Autodesk Inventor part; units mm, degrees
(part 2 of 3)
sketch "Sketch10" plane through (0, 7, 0) normal (0, 1, 0) x (1, 0, 0)
  line L0 (202.5, 101) -> (355.1, 101) projected
  arc A0 (358.1, 98) -> (355.1, 101) centre (355.1, 98) ccw projected
  line L1 (358.1, 98) -> (358.1, 72) projected
  arc A1 (355.1, 69) -> (358.1, 72) centre (355.1, 72) ccw projected
  line L2 (355.1, 69) -> (202.5, 69) projected
  arc A2 (199.5, 72) -> (202.5, 69) centre (202.5, 72) ccw projected
  line L3 (199.5, 72) -> (199.5, 98) projected
  arc A3 (202.5, 101) -> (199.5, 98) centre (202.5, 98) ccw projected
  circle A4 centre (375.1, 69) radius 2.9 projected
  circle A5 centre (375.1, 101) radius 2.9 projected
  circle A6 centre (182.5, 69) radius 2.9 projected
  circle A7 centre (182.5, 101) radius 2.9 projected
  arc A8 (200.9, 198.5) -> (195.1, 198.5) centre (198, 198.5) ccw projected
  line L4 (200.9, 198.5) -> (200.9, 195.5) projected
  arc A9 (195.1, 195.5) -> (200.9, 195.5) centre (198, 195.5) ccw projected
  line L5 (195.1, 195.5) -> (195.1, 198.5) projected
  line L6 (357, 193.5) -> (360, 193.5) projected
  line L7 (360, 193.5) -> (360, 173.5) projected
  line L8 (360, 173.5) -> (357, 173.5) projected
  line L9 (357, 173.5) -> (357, 193.5) projected
  line L10 (357, -3.5) -> (360, -3.5) projected
  line L11 (360, -3.5) -> (360, -23.5) projected
  line L12 (360, -23.5) -> (357, -23.5) projected
  line L13 (357, -23.5) -> (357, -3.5) projected
  line L14 (163, -23.5) -> (160, -23.5) projected
  line L15 (160, -23.5) -> (160, -3.5) projected
  line L16 (160, -3.5) -> (163, -3.5) projected
  line L17 (163, -3.5) -> (163, -23.5) projected
  arc A10 (345.5, -10.6) -> (345.5, -16.4) centre (345.5, -13.5) ccw projected
  line L18 (345.5, -10.6) -> (348.5, -10.6) projected
  arc A11 (348.5, -16.4) -> (348.5, -10.6) centre (348.5, -13.5) ccw projected
  line L19 (348.5, -16.4) -> (345.5, -16.4) projected
  line L20 (348.5, 180.6) -> (345.5, 180.6) projected
  arc A12 (345.5, 186.4) -> (345.5, 180.6) centre (345.5, 183.5) ccw projected
  line L21 (345.5, 186.4) -> (348.5, 186.4) projected
  arc A13 (348.5, 180.6) -> (348.5, 186.4) centre (348.5, 183.5) ccw projected
  arc A14 (174.5, 180.6) -> (174.5, 186.4) centre (174.5, 183.5) ccw projected
  line L22 (174.5, 180.6) -> (171.5, 180.6) projected
  arc A15 (171.5, 186.4) -> (171.5, 180.6) centre (171.5, 183.5) ccw projected
  line L23 (171.5, 186.4) -> (174.5, 186.4) projected
  line L24 (332.5, 210) -> (332.5, 207) projected
  line L25 (332.5, 207) -> (187.5, 207) projected
  line L26 (187.5, 207) -> (187.5, 210) projected
  line L27 (187.5, 210) -> (332.5, 210) projected
  arc A16 (324.9, -25.5) -> (319.1, -25.5) centre (322, -25.5) ccw projected
  line L28 (324.9, -25.5) -> (324.9, -28.5) projected
  arc A17 (319.1, -28.5) -> (324.9, -28.5) centre (322, -28.5) ccw projected
  line L29 (319.1, -28.5) -> (319.1, -25.5) projected
  line L30 (200.9, -25.5) -> (200.9, -28.5) projected
  arc A18 (195.1, -28.5) -> (200.9, -28.5) centre (198, -28.5) ccw projected
  line L31 (195.1, -28.5) -> (195.1, -25.5) projected
  arc A19 (200.9, -25.5) -> (195.1, -25.5) centre (198, -25.5) ccw projected
  line L32 (174.5, -16.4) -> (171.5, -16.4) projected
  arc A20 (171.5, -10.6) -> (171.5, -16.4) centre (171.5, -13.5) ccw projected
  line L33 (171.5, -10.6) -> (174.5, -10.6) projected
  arc A21 (174.5, -16.4) -> (174.5, -10.6) centre (174.5, -13.5) ccw projected
  line L34 (187.5, -40) -> (187.5, -37) projected
  line L35 (187.5, -37) -> (332.5, -37) projected
  line L36 (332.5, -37) -> (332.5, -40) projected
  line L37 (332.5, -40) -> (187.5, -40) projected
  line L38 (324.9, 198.5) -> (324.9, 195.5) projected
  arc A22 (319.1, 195.5) -> (324.9, 195.5) centre (322, 195.5) ccw projected
  line L39 (319.1, 195.5) -> (319.1, 198.5) projected
  arc A23 (324.9, 198.5) -> (319.1, 198.5) centre (322, 198.5) ccw projected
  line L40 (160, 193.5) -> (163, 193.5) projected
  line L41 (163, 193.5) -> (163, 173.5) projected
  line L42 (163, 173.5) -> (160, 173.5) projected
  line L43 (160, 173.5) -> (160, 193.5) projected
  line L44 (147.75, -60) -> (137.75, -60) projected
  line L45 (137.75, -60) -> (137.75, -57) projected
  line L46 (137.75, -57) -> (147.75, -57) projected
  line L47 (147.75, -57) -> (147.75, -60) projected
  line L48 (137.75, 4) -> (137.75, 7) projected
  line L49 (137.75, 7) -> (147.75, 7) projected
  line L50 (147.75, 7) -> (147.75, 4) projected
  line L51 (147.75, 4) -> (137.75, 4) projected
  line L52 (155.5, 29.5) -> (155.5, 14.5) projected
  line L53 (155.5, 14.5) -> (152.5, 14.5) projected
  line L54 (152.5, 14.5) -> (152.5, 29.5) projected
  line L55 (152.5, 29.5) -> (155.5, 29.5) projected
  line L56 (126.5, 136) -> (130.5, 136) projected
  line L57 (130.5, 136) -> (130.5, 133) projected
  line L58 (130.5, 133) -> (126.5, 133) projected
  line L59 (126.5, 133) -> (126.5, 136) projected
  line L60 (144, 156) -> (149, 156) projected
  line L61 (149, 156) -> (149, 153) projected
  line L62 (149, 153) -> (144, 153) projected
  line L63 (144, 153) -> (144, 156) projected
  circle A24 centre (118.59, 31.5) radius 1.25 projected
  line L64 (134.5, 139) -> (122.5, 139) projected
  arc A25 (122.5, 147) -> (122.5, 139) centre (122.5, 143) ccw projected
  line L65 (122.5, 147) -> (134.5, 147) projected
  arc A26 (134.5, 139) -> (134.5, 147) centre (134.5, 143) ccw projected
  line L66 (100.5, 138) -> (100.5, 148) projected
  line L67 (100.5, 148) -> (103.5, 148) projected
  line L68 (103.5, 148) -> (103.5, 138) projected
  line L69 (103.5, 138) -> (100.5, 138) projected
  line L70 (137.75, 40) -> (147.75, 40) projected
  line L71 (147.75, 40) -> (147.75, 37) projected
  line L72 (147.75, 37) -> (137.75, 37) projected
  line L73 (137.75, 37) -> (137.75, 40) projected
  line L74 (155.5, -34.5) -> (155.5, -49.5) projected
  line L75 (155.5, -49.5) -> (152.5, -49.5) projected
  line L76 (152.5, -49.5) -> (152.5, -34.5) projected
  line L77 (152.5, -34.5) -> (155.5, -34.5) projected
  line L78 (113.25, -60) -> (103.25, -60) projected
  line L79 (103.25, -60) -> (103.25, -57) projected
  line L80 (103.25, -57) -> (113.25, -57) projected
  line L81 (113.25, -57) -> (113.25, -60) projected
  line L82 (113.25, 4) -> (103.25, 4) projected
  line L83 (103.25, 4) -> (103.25, 7) projected
  line L84 (103.25, 7) -> (113.25, 7) projected
  line L85 (113.25, 7) -> (113.25, 4) projected
  line L86 (95.5, 14.5) -> (95.5, 29.5) projected
  line L87 (95.5, 29.5) -> (98.5, 29.5) projected
  line L88 (98.5, 29.5) -> (98.5, 14.5) projected
  line L89 (98.5, 14.5) -> (95.5, 14.5) projected
  line L90 (108, 156) -> (113, 156) projected
  line L91 (113, 156) -> (113, 153) projected
  line L92 (113, 153) -> (108, 153) projected
  line L93 (108, 153) -> (108, 156) projected
  line L94 (156.5, 138) -> (153.5, 138) projected
  line L95 (153.5, 138) -> (153.5, 148) projected
  line L96 (153.5, 148) -> (156.5, 148) projected
  line L97 (156.5, 148) -> (156.5, 138) projected
  circle A27 centre (132.41, 31.5) radius 1.25 projected
  line L98 (149, 130) -> (144, 130) projected
  line L99 (144, 130) -> (144, 133) projected
  line L100 (144, 133) -> (149, 133) projected
  line L101 (149, 133) -> (149, 130) projected
  line L102 (113, 130) -> (108, 130) projected
  line L103 (108, 130) -> (108, 133) projected
  line L104 (108, 133) -> (113, 133) projected
  line L105 (113, 133) -> (113, 130) projected
  line L106 (103.25, 40) -> (113.25, 40) projected
  line L107 (113.25, 40) -> (113.25, 37) projected
  line L108 (113.25, 37) -> (103.25, 37) projected
  line L109 (103.25, 37) -> (103.25, 40) projected
  arc A28 (135.5, -40) -> (140.5, -35) centre (135.5, -35) ccw projected
  line L110 (135.5, -40) -> (115.5, -40) projected
  arc A29 (110.5, -35) -> (115.5, -40) centre (115.5, -35) ccw projected
  line L111 (110.5, -35) -> (110.5, -25) projected
  arc A30 (115.5, -20) -> (110.5, -25) centre (115.5, -25) ccw projected
  line L112 (115.5, -20) -> (135.5, -20) projected
  arc A31 (140.5, -25) -> (135.5, -20) centre (135.5, -25) ccw projected
  line L113 (140.5, -25) -> (140.5, -35) projected
  line L114 (95.5, -49.5) -> (95.5, -34.5) projected
  line L115 (95.5, -34.5) -> (98.5, -34.5) projected
  line L116 (98.5, -34.5) -> (98.5, -49.5) projected
  line L117 (98.5, -49.5) -> (95.5, -49.5) projected
  circle A32 centre (32.5, 114.5) radius 2.75 projected
  circle A33 centre (32.5, 55.5) radius 2.75 projected
  circle A34 centre (-112.5, 155) radius 2.75 projected
  circle A35 centre (-47.5, 15) radius 2.75 projected
  circle A36 centre (-112.5, 15) radius 2.75 projected
  circle A37 centre (-47.5, 155) radius 2.75 projected
  circle A38 centre (-177.5, 155) radius 2.75 projected
  circle A39 centre (-177.5, 15) radius 2.75 projected
  line L118 (-407.5, 305) -> (-387.5, 305) projected
  line L119 (-387.5, 305) -> (-387.5, 285) projected
  line L120 (-387.5, 285) -> (-407.5, 285) projected
  line L121 (-407.5, 285) -> (-407.5, 305) projected
  arc A40 (-419, -122.1) -> (-419, -127.9) centre (-419, -125) ccw projected
  line L122 (-419, -122.1) -> (-416, -122.1) projected
  arc A41 (-416, -127.9) -> (-416, -122.1) centre (-416, -125) ccw projected
  line L123 (-416, -127.9) -> (-419, -127.9) projected
  arc A42 (100.4, -143.5) -> (94.6, -143.5) centre (97.5, -143.5) ccw projected
  line L124 (100.4, -143.5) -> (100.4, -146.5) projected
  arc A43 (94.6, -146.5) -> (100.4, -146.5) centre (97.5, -146.5) ccw projected
  line L125 (94.6, -146.5) -> (94.6, -143.5) projected
  line L126 (107.5, -115) -> (107.5, -135) projected
  line L127 (107.5, -135) -> (87.5, -135) projected
  line L128 (87.5, -135) -> (87.5, -115) projected
  line L129 (87.5, -115) -> (107.5, -115) projected
  arc A44 (100.4, 316.5) -> (94.6, 316.5) centre (97.5, 316.5) ccw projected
  line L130 (100.4, 316.5) -> (100.4, 313.5) projected
  arc A45 (94.6, 313.5) -> (100.4, 313.5) centre (97.5, 313.5) ccw projected
  line L131 (94.6, 313.5) -> (94.6, 316.5) projected
  arc A46 (76, 297.9) -> (76, 292.1) centre (76, 295) ccw projected
  line L132 (76, 297.9) -> (79, 297.9) projected
  arc A47 (79, 292.1) -> (79, 297.9) centre (79, 295) ccw projected
  line L133 (79, 292.1) -> (76, 292.1) projected
  arc A48 (116, -122.1) -> (116, -127.9) centre (116, -125) ccw projected
  line L134 (116, -122.1) -> (119, -122.1) projected
  arc A49 (119, -127.9) -> (119, -122.1) centre (119, -125) ccw projected
  line L135 (119, -127.9) -> (116, -127.9) projected
  line L136 (-387.5, -135) -> (-407.5, -135) projected
  line L137 (-407.5, -135) -> (-407.5, -115) projected
  line L138 (-407.5, -115) -> (-387.5, -115) projected
  line L139 (-387.5, -115) -> (-387.5, -135) projected
  arc A50 (-394.6, -143.5) -> (-400.4, -143.5) centre (-397.5, -143.5) ccw projected
  line L140 (-394.6, -143.5) -> (-394.6, -146.5) projected
  arc A51 (-400.4, -146.5) -> (-394.6, -146.5) centre (-397.5, -146.5) ccw projected
  line L141 (-400.4, -146.5) -> (-400.4, -143.5) projected
  arc A52 (-379, 297.9) -> (-379, 292.1) centre (-379, 295) ccw projected
  line L142 (-379, 297.9) -> (-376, 297.9) projected
  arc A53 (-376, 292.1) -> (-376, 297.9) centre (-376, 295) ccw projected
  line L143 (-376, 292.1) -> (-379, 292.1) projected
  arc A54 (-394.6, 276.5) -> (-400.4, 276.5) centre (-397.5, 276.5) ccw projected
  line L144 (-394.6, 276.5) -> (-394.6, 273.5) projected
  arc A55 (-400.4, 273.5) -> (-394.6, 273.5) centre (-397.5, 273.5) ccw projected
  line L145 (-400.4, 273.5) -> (-400.4, 276.5) projected
  arc A56 (-394.6, -103.5) -> (-400.4, -103.5) centre (-397.5, -103.5) ccw projected
  line L146 (-394.6, -103.5) -> (-394.6, -106.5) projected
  arc A57 (-400.4, -106.5) -> (-394.6, -106.5) centre (-397.5, -106.5) ccw projected
  line L147 (-400.4, -106.5) -> (-400.4, -103.5) projected
  arc A58 (76, -122.1) -> (76, -127.9) centre (76, -125) ccw projected
  line L148 (76, -122.1) -> (79, -122.1) projected
  arc A59 (79, -127.9) -> (79, -122.1) centre (79, -125) ccw projected
  line L149 (79, -127.9) -> (76, -127.9) projected
  arc A60 (116, 297.9) -> (116, 292.1) centre (116, 295) ccw projected
  line L150 (116, 297.9) -> (119, 297.9) projected
  arc A61 (119, 292.1) -> (119, 297.9) centre (119, 295) ccw projected
  line L151 (119, 292.1) -> (116, 292.1) projected
  line L152 (107.5, 305) -> (107.5, 285) projected
  line L153 (107.5, 285) -> (87.5, 285) projected
  line L154 (87.5, 285) -> (87.5, 305) projected
  line L155 (87.5, 305) -> (107.5, 305) projected
  arc A62 (100.4, 276.5) -> (94.6, 276.5) centre (97.5, 276.5) ccw projected
  line L156 (100.4, 276.5) -> (100.4, 273.5) projected
  arc A63 (94.6, 273.5) -> (100.4, 273.5) centre (97.5, 273.5) ccw projected
  line L157 (94.6, 273.5) -> (94.6, 276.5) projected
  arc A64 (100.4, -103.5) -> (94.6, -103.5) centre (97.5, -103.5) ccw projected
  line L158 (100.4, -103.5) -> (100.4, -106.5) projected
  arc A65 (94.6, -106.5) -> (100.4, -106.5) centre (97.5, -106.5) ccw projected
  line L159 (94.6, -106.5) -> (94.6, -103.5) projected
  arc A66 (-379, -122.1) -> (-379, -127.9) centre (-379, -125) ccw projected
  line L160 (-379, -122.1) -> (-376, -122.1) projected
  arc A67 (-376, -127.9) -> (-376, -122.1) centre (-376, -125) ccw projected
  line L161 (-376, -127.9) -> (-379, -127.9) projected
  line L162 (-416, 292.1) -> (-419, 292.1) projected
  arc A68 (-419, 297.9) -> (-419, 292.1) centre (-419, 295) ccw projected
  line L163 (-419, 297.9) -> (-416, 297.9) projected
  arc A69 (-416, 292.1) -> (-416, 297.9) centre (-416, 295) ccw projected
  line L164 (-400.4, 313.5) -> (-400.4, 316.5) projected
  arc A70 (-394.6, 316.5) -> (-400.4, 316.5) centre (-397.5, 316.5) ccw projected
  line L165 (-394.6, 316.5) -> (-394.6, 313.5) projected
  arc A71 (-400.4, 313.5) -> (-394.6, 313.5) centre (-397.5, 313.5) ccw projected
  line L166 (442.5, 340) -> (-442.5, 340) projected
  line L167 (-442.5, 340) -> (-442.5, -340) projected
  line L168 (-442.5, -340) -> (442.5, -340) projected
  line L169 (442.5, -340) -> (442.5, 340) projected
  line L170 (-407.5, -135) -> (107.5, -135)
  line L171 (107.5, -135) -> (107.5, 305)
  line L172 (107.5, 305) -> (-407.5, 305)
  line L173 (-407.5, 305) -> (-407.5, -135)
  line L174 (-402.5, -175) -> (257.5, -175)
  line L175 (257.5, -175) -> (257.5, -300)
  line L176 (257.5, -300) -> (-402.5, -300)
  line L177 (-402.5, -300) -> (-402.5, -175)
  line L178 (297.5, -100) -> (397.5, -100)
  line L179 (397.5, -100) -> (397.5, -300)
  line L180 (397.5, -300) -> (297.5, -300)
  line L181 (297.5, -300) -> (297.5, -100)
  line L182 (254.5, -178) -> (-399.5, -178)
  line L183 (-399.5, -178) -> (-399.5, -297)
  line L184 (-399.5, -297) -> (254.5, -297)
  line L185 (254.5, -297) -> (254.5, -178)
  line L186 (-402.5, -237.5) -> (257.5, -237.5) construction
  line L187 (-72.5, -300) -> (-72.5, -175) construction
  line L188 (-242.5, -297) -> (97.5, -297)
  line L189 (97.5, -297) -> (97.5, -300)
  line L190 (97.5, -300) -> (-242.5, -300)
  line L191 (-242.5, -300) -> (-242.5, -297)
  line L192 (97.5, -178) -> (97.5, -175)
  line L193 (-242.5, -175) -> (-242.5, -178)
  line L194 (214.5, -288.5) -> (214.5, -285.5) construction
  line L195 (217.4, -288.5) -> (217.4, -285.5)
  line L196 (211.6, -285.5) -> (211.6, -288.5)
  arc A72 (211.6, -288.5) -> (217.4, -288.5) centre (214.5, -288.5) ccw
  arc A73 (217.4, -285.5) -> (211.6, -285.5) centre (214.5, -285.5) ccw
  line L197 (-359.5, -288.5) -> (-359.5, -285.5) construction
  line L198 (-362.4, -288.5) -> (-362.4, -285.5)
  line L199 (-356.6, -285.5) -> (-356.6, -288.5)
  arc A74 (-362.4, -288.5) -> (-356.6, -288.5) centre (-359.5, -288.5) ccw
  arc A75 (-356.6, -285.5) -> (-362.4, -285.5) centre (-359.5, -285.5) ccw
  line L200 (214.5, -186.5) -> (214.5, -189.5) construction
  line L201 (217.4, -186.5) -> (217.4, -189.5)
  line L202 (211.6, -189.5) -> (211.6, -186.5)
  arc A76 (217.4, -186.5) -> (211.6, -186.5) centre (214.5, -186.5) ccw
  arc A77 (211.6, -189.5) -> (217.4, -189.5) centre (214.5, -189.5) ccw
  line L203 (-356.6, -189.5) -> (-356.6, -186.5)
  line L204 (-359.5, -186.5) -> (-359.5, -189.5) construction
  arc A78 (-362.4, -189.5) -> (-356.6, -189.5) centre (-359.5, -189.5) ccw
  arc A79 (-356.6, -186.5) -> (-362.4, -186.5) centre (-359.5, -186.5) ccw
  line L205 (-362.4, -186.5) -> (-362.4, -189.5)
  line L206 (254.5, -187.5) -> (257.5, -187.5)
  line L207 (257.5, -187.5) -> (257.5, -287.5)
  line L208 (257.5, -287.5) -> (254.5, -287.5)
  line L209 (254.5, -287.5) -> (254.5, -187.5)
  line L210 (243, -280) -> (246, -280) construction
  line L211 (243, -282.9) -> (246, -282.9)
  line L212 (246, -277.1) -> (243, -277.1)
  arc A80 (243, -277.1) -> (243, -282.9) centre (243, -280) ccw
  arc A81 (246, -282.9) -> (246, -277.1) centre (246, -280) ccw
  line L213 (-388, -280) -> (-391, -280) construction
  line L214 (-388, -282.9) -> (-391, -282.9)
  line L215 (-391, -277.1) -> (-388, -277.1)
  arc A82 (-388, -282.9) -> (-388, -277.1) centre (-388, -280) ccw
  arc A83 (-391, -277.1) -> (-391, -282.9) centre (-391, -280) ccw
  line L216 (243, -195) -> (246, -195) construction
  line L217 (243, -192.1) -> (246, -192.1)
  line L218 (246, -197.9) -> (243, -197.9)
  arc A84 (243, -192.1) -> (243, -197.9) centre (243, -195) ccw
  arc A85 (246, -197.9) -> (246, -192.1) centre (246, -195) ccw
  line L219 (-388, -192.1) -> (-391, -192.1)
  line L220 (-388, -195) -> (-391, -195) construction
  line L221 (-391, -197.9) -> (-388, -197.9)
  arc A86 (-388, -197.9) -> (-388, -192.1) centre (-388, -195) ccw
  arc A87 (-391, -192.1) -> (-391, -197.9) centre (-391, -195) ccw
  line L222 (-399.5, -187.5) -> (-402.5, -187.5)
  line L223 (-402.5, -287.5) -> (-399.5, -287.5)
  line L224 (394.5, -297) -> (394.5, -103)
  line L225 (394.5, -103) -> (300.5, -103)
  line L226 (300.5, -103) -> (300.5, -297)
  line L227 (300.5, -297) -> (394.5, -297)
  line L228 (347.5, -100) -> (347.5, -300) construction
  line L229 (297.5, -200) -> (397.5, -200) construction
  line L230 (322.5, -100) -> (372.5, -100)
  line L231 (372.5, -100) -> (372.5, -103)
  line L232 (372.5, -103) -> (322.5, -103)
  line L233 (322.5, -103) -> (322.5, -100)
  line L234 (315.5, -111.5) -> (315.5, -114.5) construction
  line L235 (312.6, -111.5) -> (312.6, -114.5)
  line L236 (318.4, -114.5) -> (318.4, -111.5)
  arc A88 (318.4, -111.5) -> (312.6, -111.5) centre (315.5, -111.5) ccw
  arc A89 (312.6, -114.5) -> (318.4, -114.5) centre (315.5, -114.5) ccw
  line L237 (379.5, -111.5) -> (379.5, -114.5) construction
  line L238 (382.4, -111.5) -> (382.4, -114.5)
  line L239 (376.6, -114.5) -> (376.6, -111.5)
  arc A90 (382.4, -111.5) -> (376.6, -111.5) centre (379.5, -111.5) ccw
  arc A91 (376.6, -114.5) -> (382.4, -114.5) centre (379.5, -114.5) ccw
  line L240 (372.5, -300) -> (372.5, -297)
  line L241 (322.5, -297) -> (322.5, -300)
  line L242 (315.5, -288.5) -> (315.5, -285.5) construction
  line L243 (312.6, -288.5) -> (312.6, -285.5)
  line L244 (318.4, -285.5) -> (318.4, -288.5)
  arc A92 (312.6, -288.5) -> (318.4, -288.5) centre (315.5, -288.5) ccw
  arc A93 (318.4, -285.5) -> (312.6, -285.5) centre (315.5, -285.5) ccw
  arc A94 (382.4, -285.5) -> (376.6, -285.5) centre (379.5, -285.5) ccw
  line L245 (376.6, -285.5) -> (376.6, -288.5)
  line L246 (379.5, -288.5) -> (379.5, -285.5) construction
  line L247 (382.4, -288.5) -> (382.4, -285.5)
  arc A95 (376.6, -288.5) -> (382.4, -288.5) centre (379.5, -288.5) ccw
  line L248 (297.5, -150) -> (300.5, -150)
  line L249 (300.5, -150) -> (300.5, -250)
  line L250 (300.5, -250) -> (297.5, -250)
  line L251 (297.5, -250) -> (297.5, -150)
  line L252 (309, -138) -> (312, -138) construction
  line L253 (309, -140.9) -> (312, -140.9)
  line L254 (312, -135.1) -> (309, -135.1)
  arc A96 (309, -135.1) -> (309, -140.9) centre (309, -138) ccw
  arc A97 (312, -140.9) -> (312, -135.1) centre (312, -138) ccw
  line L255 (309, -262) -> (312, -262) construction
  line L256 (309, -259.1) -> (312, -259.1)
  line L257 (312, -264.9) -> (309, -264.9)
  arc A98 (309, -259.1) -> (309, -264.9) centre (309, -262) ccw
  arc A99 (312, -264.9) -> (312, -259.1) centre (312, -262) ccw
  line L258 (397.5, -150) -> (394.5, -150)
  line L259 (394.5, -250) -> (397.5, -250)
  line L260 (386, -138) -> (383, -138) construction
  line L261 (386, -140.9) -> (383, -140.9)
  line L262 (383, -135.1) -> (386, -135.1)
  arc A100 (386, -140.9) -> (386, -135.1) centre (386, -138) ccw
  arc A101 (383, -135.1) -> (383, -140.9) centre (383, -138) ccw
  line L263 (386, -259.1) -> (383, -259.1)
  arc A102 (386, -264.9) -> (386, -259.1) centre (386, -262) ccw
  line L264 (386, -262) -> (383, -262) construction
  arc A103 (383, -259.1) -> (383, -264.9) centre (383, -262) ccw
  line L265 (383, -264.9) -> (386, -264.9)
  point P0 (0, 0)
  point P1 (214.5, -287)
  point P2 (-359.5, -287)
  point P3 (214.5, -188)
  point P4 (-359.5, -188)
  point P5 (254.5, -237.5)
  point P6 (254.5, -237.5)
  point P7 (244.5, -280)
  point P8 (-389.5, -280)
  point P9 (244.5, -195)
  point P10 (-389.5, -195)
  point P11 (347.5, -103)
  point P12 (347.5, -103)
  point P13 (315.5, -113)
  point P14 (379.5, -113)
  point P15 (315.5, -287)
  point P16 (379.5, -287)
  point P17 (300.5, -200)
  point P18 (300.5, -200)
  point P19 (310.5, -138)
  point P20 (310.5, -262)
  point P21 (384.5, -138)
  point P22 (384.5, -262)
  point P23 (322.5, -103)
  point P24 (300.5, -150)
  point P25 (-402.5, -187.5)
  point P26 (-402.5, -287.5)
  point P27 (97.5, -297)
  point P28 (97.5, -178)
  point P29 (97.5, -175)
  point P30 (-242.5, -175)
  point P31 (257.5, -187.5)
  dimension "d188" = 125
  dimension "d189" = 660
  dimension "d190" = 40
  dimension "d191" = 40
  dimension "d192" = 100
  dimension "d193" = 200
  dimension "d194" = 40
  dimension "d195" = 40
  dimension "d196" = 3
  dimension "d197" = 340
  dimension "d198" = 3
  dimension "d199" = 5.8
  dimension "d200" = 8.5
  dimension "d201" = 40
  dimension "d202" = 100
  dimension "d203" = 3
  dimension "d204" = 5.8
  dimension "d205" = 8.5
  dimension "d206" = 20
  dimension "d207" = 3
  dimension "d208" = 50
  dimension "d209" = 3
  dimension "d210" = 5.8
  dimension "d211" = 8.5
  dimension "d212" = 15
  dimension "d213" = 100
  dimension "d214" = 3
  dimension "d215" = 5.8
  dimension "d216" = 8.5
  dimension "d217" = 35
  constraints: 224 end point, 100 symmetric about line, 64 point on circle, 32 centre point, 23 parallel, 19 midpoint, 16 tangent, 9 perpendicular, 8 horizontal, 8 point on line, 4 coincident, 1 vertical, 30 other
  measures "d188" distance of L176.end L174.start
  measures "d189" distance of L175.end L176.end
  measures "d190" distance between parallel lines of L167 L177
  measures "d191" distance between parallel lines of L168 L176
  measures "d192" distance of L179.end L180.end
  measures "d193" distance of L180.end L178.start
  measures "d194" distance between parallel lines of L168 L180
  measures "d195" distance between parallel lines of L175 L181
  measures "d196" distance between parallel lines of L174 L182
  measures "d197" distance between parallel lines of L191 L189
  measures "d198" distance of L194.start L194.end
  measures "d199" diameter of A73
  measures "d200" distance from line of L184 L194.start
  measures "d201" distance between parallel lines of L185 L194
  measures "d202" distance between parallel lines of L208 L206
  measures "d203" distance of L210.start L210.end
  measures "d204" diameter of A81
  measures "d205" distance from line of L209 L210.end
  measures "d206" distance between parallel lines of L176 L210
  measures "d207" distance between parallel lines of L179 L224
  measures "d208" distance of L231.end L232.end
  measures "d209" distance of L234.start L234.end
  measures "d210" diameter of A89
  measures "d211" distance from line of L225 L234.start
  measures "d212" distance between parallel lines of L226 L234
  measures "d213" distance of L248.end L249.end
  measures "d214" distance of L252.start L252.end
  measures "d215" diameter of A97
  measures "d216" distance from line of L226 L252.start
  measures "d217" distance between parallel lines of L225 L252
extrude "Extrusion6" cut sketch "Sketch10" against normal blind 10 contours L174 L192 L182 L193 | L222 L183 L223 L177 | L175 L208 L185 L206 | L191 L184 L189 L176 | L178 L231 L225 L233 | L248 L226 L250 L181 | L179 L259 L224 L258 | L241 L227 L240 L180 | A72 L196 A73 L195 | L198 A75 L199 A74 | L201 A77 L202 A76 | A78 L205 A79 L203 | A80 L212 A81 L211 | L214 A83 L215 A82 | L217 A85 L218 A84 | A86 L221 A87 L219 | A88 L236 A89 L235 | L238 A91 L239 A90 | L243 A93 L244 A92 | L247 A95 L245 A94 | A96 L254 A97 L253 | L256 A99 L257 A98 | L261 A101 L262 A100 | A102 L265 A103 L263
sketch "Sketch11" plane through (0, 7, 0) normal (0, 1, 0) x (1, 0, 0)
  line L0 (442.5, 340) -> (-442.5, 340) projected
  line L1 (-442.5, -340) -> (442.5, -340) projected
  line L2 (-442.5, 340) -> (-435.5, 340)
  line L3 (-435.5, 340) -> (-435.5, -340)
  line L4 (-435.5, -340) -> (-442.5, -340)
  line L5 (-442.5, -340) -> (-442.5, 340)
  line L6 (-442.5, 340) -> (-435.5, 340)
  line L7 (-435.5, 340) -> (-435.5, 300)
  line L8 (-435.5, 300) -> (-442.5, 300)
  line L9 (-442.5, 300) -> (-442.5, 340)
  line L10 (-442.5, 300) -> (-435.5, 300)
  line L11 (-435.5, 300) -> (-435.5, 260)
  line L12 (-435.5, 260) -> (-442.5, 260)
  line L13 (-442.5, 260) -> (-442.5, 300)
  line L14 (0, 340) -> (0, -340) construction
  line L15 (-435.5, 220) -> (-442.5, 220)
  line L16 (-435.5, 180) -> (-442.5, 180)
  line L17 (-435.5, 140) -> (-442.5, 140)
  line L18 (-435.5, 100) -> (-442.5, 100)
  line L19 (-435.5, 60) -> (-442.5, 60)
  line L20 (-435.5, 20) -> (-442.5, 20)
  line L21 (-435.5, -20) -> (-442.5, -20)
  line L22 (-435.5, -60) -> (-442.5, -60)
  line L23 (-435.5, -100) -> (-442.5, -100)
  line L24 (-435.5, -140) -> (-442.5, -140)
  line L25 (-435.5, -180) -> (-442.5, -180)
  line L26 (-435.5, -220) -> (-442.5, -220)
  line L27 (-435.5, -260) -> (-442.5, -260)
  line L28 (-435.5, -300) -> (-442.5, -300)
  line L29 (442.5, 340) -> (435.5, 340)
  line L30 (435.5, 340) -> (435.5, -340)
  line L31 (435.5, -340) -> (442.5, -340)
  line L32 (442.5, -340) -> (442.5, 340)
  line L33 (442.5, 340) -> (435.5, 340)
  line L34 (435.5, 340) -> (435.5, 300)
  line L35 (435.5, 300) -> (442.5, 300)
  line L36 (442.5, 300) -> (442.5, 340)
  line L37 (442.5, 300) -> (435.5, 300)
  line L38 (435.5, 300) -> (435.5, 260)
  line L39 (435.5, 260) -> (442.5, 260)
  line L40 (442.5, 260) -> (442.5, 300)
  line L41 (435.5, 220) -> (442.5, 220)
  line L42 (435.5, 180) -> (442.5, 180)
  line L43 (435.5, 140) -> (442.5, 140)
  line L44 (435.5, 100) -> (442.5, 100)
  line L45 (435.5, 60) -> (442.5, 60)
  line L46 (435.5, 20) -> (442.5, 20)
  line L47 (435.5, -20) -> (442.5, -20)
  line L48 (435.5, -60) -> (442.5, -60)
  line L49 (435.5, -100) -> (442.5, -100)
  line L50 (435.5, -140) -> (442.5, -140)
  line L51 (435.5, -180) -> (442.5, -180)
  line L52 (435.5, -220) -> (442.5, -220)
  line L53 (435.5, -260) -> (442.5, -260)
  line L54 (435.5, -300) -> (442.5, -300)
  line L55 (-442.5, 340) -> (442.5, 340)
  line L56 (442.5, 340) -> (442.5, 333)
  line L57 (442.5, 333) -> (-442.5, 333)
  line L58 (-442.5, 333) -> (-442.5, 340)
  line L59 (-442.5, 340) -> (-383.5, 340)
  line L60 (-383.5, 340) -> (-383.5, 333)
  line L61 (-383.5, 333) -> (-442.5, 333)
  line L62 (-442.5, 333) -> (-442.5, 340)
  line L63 (-383.5, 340) -> (-324.5, 340)
  line L64 (-324.5, 340) -> (-324.5, 333)
  line L65 (-324.5, 333) -> (-383.5, 333)
  line L66 (-383.5, 333) -> (-383.5, 340)
  line L67 (-442.5, 0) -> (442.5, 0) construction
  line L68 (-265.5, 340) -> (-265.5, 333)
  line L69 (-206.5, 340) -> (-206.5, 333)
  line L70 (-147.5, 340) -> (-147.5, 333)
  line L71 (-88.5, 340) -> (-88.5, 333)
  line L72 (-29.5, 340) -> (-29.5, 333)
  line L73 (29.5, 340) -> (29.5, 333)
  line L74 (88.5, 340) -> (88.5, 333)
  line L75 (147.5, 340) -> (147.5, 333)
  line L76 (206.5, 340) -> (206.5, 333)
  line L77 (265.5, 340) -> (265.5, 333)
  line L78 (324.5, 340) -> (324.5, 333)
  line L79 (383.5, 340) -> (383.5, 333)
  line L80 (-383.5, -340) -> (-383.5, -333)
  line L81 (-324.5, -340) -> (-324.5, -333)
  line L82 (-265.5, -340) -> (-265.5, -333)
  line L83 (-206.5, -340) -> (-206.5, -333)
  line L84 (-147.5, -340) -> (-147.5, -333)
  line L85 (-88.5, -340) -> (-88.5, -333)
  line L86 (-29.5, -340) -> (-29.5, -333)
  line L87 (29.5, -340) -> (29.5, -333)
  line L88 (88.5, -340) -> (88.5, -333)
  line L89 (147.5, -340) -> (147.5, -333)
  line L90 (206.5, -340) -> (206.5, -333)
  line L91 (265.5, -340) -> (265.5, -333)
  line L92 (324.5, -340) -> (324.5, -333)
  line L93 (383.5, -340) -> (383.5, -333)
  line L94 (442.5, -333) -> (-442.5, -333)
  point P0 (435.5, -300)
  point P1 (442.5, -300)
  point P2 (442.5, -260)
  point P3 (435.5, -260)
  point P4 (435.5, -220)
  point P5 (442.5, -220)
  point P6 (442.5, -180)
  point P7 (435.5, -180)
  point P8 (442.5, -100)
  point P9 (435.5, -100)
  point P10 (435.5, -140)
  point P11 (442.5, -140)
  point P12 (435.5, -60)
  point P13 (442.5, -60)
  point P14 (442.5, -20)
  point P15 (435.5, -20)
  point P16 (442.5, 60)
  point P17 (442.5, 20)
  point P18 (442.5, 100)
  point P19 (442.5, 140)
  point P20 (442.5, 180)
  point P21 (442.5, 220)
  point P22 (442.5, 260)
  point P23 (442.5, 300)
  point P24 (383.5, 340)
  point P25 (324.5, 340)
  point P26 (324.5, 333)
  point P27 (265.5, 340)
  point P28 (206.5, 340)
  point P29 (206.5, 333)
  point P30 (147.5, 340)
  point P31 (88.5, 340)
  point P32 (88.5, 333)
  point P33 (29.5, 340)
  point P34 (-29.5, 340)
  point P35 (-29.5, 333)
  point P36 (-88.5, 340)
  point P37 (-147.5, 340)
  point P38 (-147.5, 333)
  point P39 (-206.5, 340)
  point P40 (-265.5, 333)
  point P41 (-442.5, 260)
  point P42 (-442.5, 300)
  point P43 (-442.5, 180)
  point P44 (-442.5, 220)
  point P45 (-442.5, 100)
  point P46 (-442.5, 140)
  point P47 (-442.5, 20)
  point P48 (-442.5, 60)
  point P49 (-442.5, -60)
  point P50 (-435.5, -60)
  point P51 (-435.5, -20)
  point P52 (-442.5, -20)
  point P53 (-442.5, -140)
  point P54 (-435.5, -140)
  point P55 (-435.5, -100)
  point P56 (-442.5, -100)
  point P57 (-442.5, -220)
  point P58 (-435.5, -220)
  point P59 (-435.5, -180)
  point P60 (-442.5, -180)
  point P61 (-442.5, -300)
  point P62 (-435.5, -300)
  point P63 (-435.5, -260)
  point P64 (-442.5, -260)
  point P65 (-383.5, -333)
  point P66 (-265.5, -333)
  point P67 (-147.5, -333)
  point P68 (-29.5, -333)
  point P69 (88.5, -333)
  point P70 (206.5, -333)
  point P71 (324.5, -333)
  point P72 (435.5, 333)
  point P73 (-435.5, 333)
  point P74 (-435.5, -333)
  point P75 (435.5, -333)
  dimension "d240" = 7
  dimension "d241" = 40
  dimension "d242" = 40
  dimension "d245" = 80
  dimension "d250" = 7
  dimension "d251" = 59
  dimension "d252" = 59
  dimension "d255" = 118
  constraints: 176 end point, 68 symmetric about line, 11 parallel, 8 horizontal, 5 perpendicular, 3 point on line, 1 vertical, 104 other
  measures "d240" distance of L4.start L4.end
  measures "d241" distance of L6.end L7.end
  measures "d242" distance of L10.end L11.end
  measures "d245" distance of L7.end L15.start
  measures "d250" distance of L55.end L56.end
  measures "d251" distance of L60.end L61.end
  measures "d252" distance of L64.end L65.end
  measures "d255" distance of L59.end L68.start
extrude "Extrusion7" cut sketch "Sketch11" against normal blind 10 contours L79 L57 L78 L0 | L32 L39 L30 L35 | L77 L57 L76 L0 | L32 L42 L30 L41 | L75 L57 L74 L0 | L32 L44 L30 L43 | L73 L57 L72 L0 | L32 L46 L30 L45 | L71 L57 L70 L0 | L32 L48 L30 L47 | L69 L57 L68 L0 | L32 L50 L30 L49 | L64 L57 L60 L0 | L32 L52 L30 L51 | L32 L54 L30 L53 | L3 L12 L5 L8 | L3 L16 L5 L15 | L93 L1 L92 L94 | L3 L18 L5 L17 | L91 L1 L90 L94 | L3 L20 L5 L19 | L89 L1 L88 L94 | L3 L22 L5 L21 | L87 L1 L86 L94 | L3 L24 L5 L23 | L85 L1 L84 L94 | L3 L26 L5 L25 | L83 L1 L82 L94 | L3 L28 L5 L27 | L81 L1 L80 L94
fillet "Fillet1" radius 7 4 edges at (442.5, 3.5, 340) (442.5, 3.5, -340) (-442.5, 3.5, -340) (-442.5, 3.5, 340)
sketch "Sketch12" plane through (0, 7, 0) normal (0, 1, 0) x (1, 0, 0)
  line L0 (-335.5, 324.5) -> (-335.5, 321.5) construction
  line L1 (-338.4, 324.5) -> (-338.4, 321.5)
  line L2 (-332.6, 321.5) -> (-332.6, 324.5)
  arc A0 (-332.6, 324.5) -> (-338.4, 324.5) centre (-335.5, 324.5) ccw
  arc A1 (-338.4, 321.5) -> (-332.6, 321.5) centre (-335.5, 321.5) ccw
  line L3 (-324.5, 333) -> (-383.5, 333) projected
  line L4 (-435.5, 300) -> (-435.5, 260) projected
  line L5 (-442.5, 20) -> (-442.5, -20) projected
  line L6 (-442.5, 0) -> (442.5, 0) construction
  line L7 (442.5, -20) -> (442.5, 20) projected
  line L8 (335.5, 324.5) -> (335.5, 321.5) construction
  line L9 (332.6, 324.5) -> (332.6, 321.5)
  line L10 (338.4, 321.5) -> (338.4, 324.5)
  arc A2 (338.4, 324.5) -> (332.6, 324.5) centre (335.5, 324.5) ccw
  arc A3 (332.6, 321.5) -> (338.4, 321.5) centre (335.5, 321.5) ccw
  line L11 (383.5, 333) -> (324.5, 333) projected
  line L12 (435.5, 260) -> (435.5, 300) projected
  line L13 (-185.5, 324.5) -> (-185.5, 321.5) construction
  line L14 (-188.4, 324.5) -> (-188.4, 321.5)
  line L15 (-182.6, 321.5) -> (-182.6, 324.5)
  arc A4 (-182.6, 324.5) -> (-188.4, 324.5) centre (-185.5, 324.5) ccw
  arc A5 (-188.4, 321.5) -> (-182.6, 321.5) centre (-185.5, 321.5) ccw
  line L16 (-206.5, 333) -> (-265.5, 333) projected
  line L17 (185.5, 324.5) -> (185.5, 321.5) construction
  line L18 (182.6, 324.5) -> (182.6, 321.5)
  line L19 (188.4, 321.5) -> (188.4, 324.5)
  arc A6 (188.4, 324.5) -> (182.6, 324.5) centre (185.5, 324.5) ccw
  arc A7 (182.6, 321.5) -> (188.4, 321.5) centre (185.5, 321.5) ccw
  line L20 (265.5, 333) -> (206.5, 333) projected
  line L21 (0, 324.5) -> (0, 321.5) construction
  line L22 (-2.9, 324.5) -> (-2.9, 321.5)
  line L23 (2.9, 321.5) -> (2.9, 324.5)
  arc A8 (2.9, 324.5) -> (-2.9, 324.5) centre (0, 324.5) ccw
  arc A9 (-2.9, 321.5) -> (2.9, 321.5) centre (0, 321.5) ccw
  line L24 (29.5, 333) -> (-29.5, 333) projected
  line L25 (-335.5, -324.5) -> (-335.5, -321.5) construction
  line L26 (-338.4, -324.5) -> (-338.4, -321.5)
  line L27 (-332.6, -321.5) -> (-332.6, -324.5)
  arc A10 (-338.4, -324.5) -> (-332.6, -324.5) centre (-335.5, -324.5) ccw
  arc A11 (-332.6, -321.5) -> (-338.4, -321.5) centre (-335.5, -321.5) ccw
  line L28 (335.5, -324.5) -> (335.5, -321.5) construction
  line L29 (332.6, -324.5) -> (332.6, -321.5)
  line L30 (338.4, -321.5) -> (338.4, -324.5)
  arc A12 (332.6, -324.5) -> (338.4, -324.5) centre (335.5, -324.5) ccw
  arc A13 (338.4, -321.5) -> (332.6, -321.5) centre (335.5, -321.5) ccw
  line L31 (-185.5, -324.5) -> (-185.5, -321.5) construction
  line L32 (-188.4, -324.5) -> (-188.4, -321.5)
  line L33 (-182.6, -321.5) -> (-182.6, -324.5)
  arc A14 (-188.4, -324.5) -> (-182.6, -324.5) centre (-185.5, -324.5) ccw
  arc A15 (-182.6, -321.5) -> (-188.4, -321.5) centre (-185.5, -321.5) ccw
  line L34 (185.5, -324.5) -> (185.5, -321.5) construction
  line L35 (182.6, -324.5) -> (182.6, -321.5)
  line L36 (188.4, -321.5) -> (188.4, -324.5)
  arc A16 (182.6, -324.5) -> (188.4, -324.5) centre (185.5, -324.5) ccw
  arc A17 (188.4, -321.5) -> (182.6, -321.5) centre (185.5, -321.5) ccw
  line L37 (0, -324.5) -> (0, -321.5) construction
  line L38 (-2.9, -324.5) -> (-2.9, -321.5)
  line L39 (2.9, -321.5) -> (2.9, -324.5)
  arc A18 (-2.9, -324.5) -> (2.9, -324.5) centre (0, -324.5) ccw
  arc A19 (2.9, -321.5) -> (-2.9, -321.5) centre (0, -321.5) ccw
  line L40 (0, 333) -> (0, -333) construction
  line L41 (-29.5, -333) -> (29.5, -333) projected
  line L42 (-427, 240) -> (-424, 240) construction
  line L43 (-427, 237.1) -> (-424, 237.1)
  line L44 (-424, 242.9) -> (-427, 242.9)
  arc A20 (-427, 242.9) -> (-427, 237.1) centre (-427, 240) ccw
  arc A21 (-424, 237.1) -> (-424, 242.9) centre (-424, 240) ccw
  line L45 (-383.5, 340) -> (-435.5, 340) projected
  line L46 (-427, 80) -> (-424, 80) construction
  line L47 (-427, 77.1) -> (-424, 77.1)
  line L48 (-424, 82.9) -> (-427, 82.9)
  arc A22 (-427, 82.9) -> (-427, 77.1) centre (-427, 80) ccw
  arc A23 (-424, 77.1) -> (-424, 82.9) centre (-424, 80) ccw
  line L49 (-435.5, 220) -> (-435.5, 180) projected
  line L50 (-427, -240) -> (-424, -240) construction
  line L51 (-427, -237.1) -> (-424, -237.1)
  line L52 (-424, -242.9) -> (-427, -242.9)
  arc A24 (-427, -237.1) -> (-427, -242.9) centre (-427, -240) ccw
  arc A25 (-424, -242.9) -> (-424, -237.1) centre (-424, -240) ccw
  line L53 (-427, -80) -> (-424, -80) construction
  line L54 (-427, -77.1) -> (-424, -77.1)
  line L55 (-424, -82.9) -> (-427, -82.9)
  arc A26 (-427, -77.1) -> (-427, -82.9) centre (-427, -80) ccw
  arc A27 (-424, -82.9) -> (-424, -77.1) centre (-424, -80) ccw
  line L56 (-435.5, 60) -> (-435.5, 20) projected
  circle A28 centre (-335.5, 321.5) radius 1
  circle A29 centre (-185.5, 321.5) radius 1
  circle A30 centre (0, 321.5) radius 1
  circle A31 centre (185.5, 321.5) radius 1
  circle A32 centre (335.5, 321.5) radius 1
  circle A33 centre (-424, 240) radius 1
  circle A34 centre (-424, 80) radius 1
  circle A35 centre (-335.5, -321.5) radius 1
  circle A36 centre (-185.5, -321.5) radius 1
  circle A37 centre (0, -321.5) radius 1
  circle A38 centre (185.5, -321.5) radius 1
  circle A39 centre (335.5, -321.5) radius 1
  circle A40 centre (-424, -240) radius 1
  circle A41 centre (-424, -80) radius 1
  circle A42 centre (-335.5, 184.5) radius 1
  circle A43 centre (-185.5, 184.5) radius 1
  circle A44 centre (0, 184.5) radius 1
  circle A45 centre (185.5, 184.5) radius 1
  circle A46 centre (335.5, 184.5) radius 1
  circle A47 centre (-335.5, -79.5) radius 1
  circle A48 centre (-185.5, -79.5) radius 1
  circle A49 centre (0, -79.5) radius 1
  circle A50 centre (185.5, -79.5) radius 1
  circle A51 centre (335.5, -79.5) radius 1
  point P0 (0, 0)
  point P1 (-335.5, 323)
  point P2 (335.5, 323)
  point P3 (-185.5, 323)
  point P4 (185.5, 323)
  point P5 (0, 323)
  point P6 (-335.5, -323)
  point P7 (335.5, -323)
  point P8 (-185.5, -323)
  point P9 (185.5, -323)
  point P10 (0, -323)
  point P11 (-425.5, 240)
  point P12 (-425.5, 80)
  point P13 (-425.5, -240)
  point P14 (-425.5, -80)
  dimension "d274" = 3
  dimension "d275" = 5.8
  dimension "d276" = 8.5
  dimension "d277" = 100
  dimension "d278" = 3
  dimension "d279" = 5.8
  dimension "d280" = 8.5
  dimension "d281" = 100
  dimension "d282" = 3
  dimension "d283" = 5.8
  dimension "d284" = 8.5
  dimension "d285" = 150
  dimension "d286" = 3
  dimension "d287" = 5.8
  dimension "d288" = 8.5
  dimension "d289" = 150
  dimension "d290" = 3
  dimension "d291" = 5.8
  dimension "d292" = 8.5
  dimension "d293" = 3
  dimension "d294" = 5.8
  dimension "d295" = 8.5
  dimension "d296" = 100
  dimension "d297" = 3
  dimension "d298" = 5.8
  dimension "d299" = 8.5
  dimension "d300" = 160
  dimension "d306" = 2
  dimension "d307" = 2
  dimension "d308" = 2
  dimension "d309" = 2
  dimension "d310" = 2
  dimension "d311" = 2
  dimension "d312" = 2
  dimension "d315" = 137
  dimension "d322" = 242
  constraints: 116 end point, 56 point on circle, 56 symmetric about line, 52 centre point, 28 tangent, 11 midpoint, 7 coincident, 7 parallel, 7 vertical, 2 horizontal, 1 vertical alignment, 41 other
  measures "d274" distance of L0.start L0.end
  measures "d275" diameter of A1
  measures "d276" distance from line of L3 L0.start
  measures "d277" distance between parallel lines of L4 L0
  measures "d278" distance of L8.start L8.end
  measures "d279" diameter of A3
  measures "d280" distance from line of L11 L8.start
  measures "d281" distance between parallel lines of L12 L8
  measures "d282" distance of L13.start L13.end
  measures "d283" diameter of A5
  measures "d284" distance from line of L16 L13.start
  measures "d285" distance between parallel lines of L0 L13
  measures "d286" distance of L17.start L17.end
  measures "d287" diameter of A7
  measures "d288" distance from line of L20 L17.start
  measures "d289" distance between parallel lines of L8 L17
  measures "d290" distance of L21.start L21.end
  measures "d291" diameter of A9
  measures "d292" distance from line of L24 L21.start
  measures "d293" distance of L42.start L42.end
  measures "d294" diameter of A21
  measures "d295" distance from line of L4 L42.start
  measures "d296" distance between parallel lines of L45 L42
  measures "d297" distance of L46.start L46.end
  measures "d298" diameter of A23
  measures "d299" distance from line of L49 L46.start
  measures "d300" distance between parallel lines of L42 L46
  measures "d306" diameter of A28
  measures "d307" diameter of A29
  measures "d308" diameter of A30
  measures "d309" diameter of A31
  measures "d310" diameter of A32
  measures "d311" diameter of A33
  measures "d312" diameter of A34
  measures "d315" distance of A28.centre A42.centre
  measures "d322" distance of A35.centre A47.centre
extrude "Extrusion8" cut sketch "Sketch12" against normal through all contours A28 | A29 | A30 | A31 | A32 | A33 | A34 | A35 | A36 | A37 | A38 | A39 | A40 | A41 | A42 | A43 | A44 | A45 | A46 | A47 | A48 | A49 | A50 | A51
sketch "Sketch13" plane through (0, 7, 0) normal (0, 1, 0) x (1, 0, 0)
  line L0 (-373.5, -243) -> (-369.5, -243) construction
  line L1 (-373.5, -245.75) -> (-369.5, -245.75)
  line L2 (-369.5, -240.25) -> (-373.5, -240.25)
  arc A0 (-373.5, -240.25) -> (-373.5, -245.75) centre (-373.5, -243) ccw
  arc A1 (-369.5, -245.75) -> (-369.5, -240.25) centre (-369.5, -243) ccw
  line L3 (-282.4, -243) -> (-278.4, -243) construction
  line L4 (-282.4, -244.125) -> (-278.4, -244.125)
  line L5 (-278.4, -241.875) -> (-282.4, -241.875)
  arc A2 (-282.4, -241.875) -> (-282.4, -244.125) centre (-282.4, -243) ccw
  arc A3 (-278.4, -244.125) -> (-278.4, -241.875) centre (-278.4, -243) ccw
  line L6 (-242.5, -297) -> (97.5, -297) projected
  line L7 (-299.5, -205.5) -> (0.5, -205.5) construction
  line L8 (-299.5, -213) -> (0.5, -213)
  line L9 (0.5, -198) -> (-299.5, -198)
  arc A4 (-299.5, -198) -> (-299.5, -213) centre (-299.5, -205.5) ccw
  arc A5 (0.5, -213) -> (0.5, -198) centre (0.5, -205.5) ccw
  line L10 (97.5, -178) -> (-242.5, -178) projected
  line L11 (-399.5, -187.5) -> (-399.5, -287.5) projected
  line L12 (-252.4, -243) -> (-248.4, -243) construction
  line L13 (-252.4, -244.125) -> (-248.4, -244.125)
  line L14 (-248.4, -241.875) -> (-252.4, -241.875)
  arc A6 (-252.4, -241.875) -> (-252.4, -244.125) centre (-252.4, -243) ccw
  arc A7 (-248.4, -244.125) -> (-248.4, -241.875) centre (-248.4, -243) ccw
  line L15 (-161.3, -243) -> (-157.3, -243) construction
  line L16 (-161.3, -244.125) -> (-157.3, -244.125)
  line L17 (-157.3, -241.875) -> (-161.3, -241.875)
  arc A8 (-161.3, -241.875) -> (-161.3, -244.125) centre (-161.3, -243) ccw
  arc A9 (-157.3, -244.125) -> (-157.3, -241.875) centre (-157.3, -243) ccw
  line L18 (332.5, -247) -> (362.5, -247) construction
  line L19 (332.5, -262) -> (362.5, -262)
  line L20 (362.5, -232) -> (332.5, -232)
  arc A10 (332.5, -232) -> (332.5, -262) centre (332.5, -247) ccw
  arc A11 (362.5, -262) -> (362.5, -232) centre (362.5, -247) ccw
  line L21 (322.5, -297) -> (372.5, -297) projected
  line L22 (-126.175, -276) -> (-83.175, -276)
  line L23 (-83.175, -276) -> (-83.175, -233)
  line L24 (-83.175, -233) -> (-126.175, -233)
  line L25 (-126.175, -233) -> (-126.175, -276)
  line L26 (-126.175, -276) -> (-83.175, -233) construction
  line L27 (-83.175, -276) -> (-126.175, -233) construction
  circle A12 centre (-86.175, -236) radius 1.65
  circle A13 centre (-86.175, -273) radius 1.65
  line L28 (-104.675, -233) -> (-104.675, -276) construction
  line L29 (-126.175, -254.5) -> (-83.175, -254.7529) construction
  circle A14 centre (-123.175, -236) radius 1.65
  circle A15 centre (-123.175, -273) radius 1.65
  line L30 (-63.175, -286) -> (13.825, -286)
  line L31 (13.825, -286) -> (13.825, -223)
  line L32 (13.825, -223) -> (-63.175, -223)
  line L33 (-63.175, -223) -> (-63.175, -286)
  line L34 (-63.175, -254.5) -> (13.825, -254.5) construction
  line L35 (-24.675, -223) -> (-24.675, -286) construction
  circle A16 centre (-59.675, -226.5) radius 1.5
  circle A17 centre (-59.675, -282.5) radius 1.5
  circle A18 centre (10.325, -226.5) radius 1.5
  circle A19 centre (10.325, -282.5) radius 1.5
  line L36 (307.5, -216) -> (384.5, -216)
  line L37 (384.5, -216) -> (384.5, -153)
  line L38 (384.5, -153) -> (307.5, -153)
  line L39 (307.5, -153) -> (307.5, -216)
  line L40 (307.5, -184.5) -> (384.5, -184.5) construction
  line L41 (346, -153) -> (346, -216) construction
  circle A20 centre (311, -156.5) radius 1.5
  circle A21 centre (311, -212.5) radius 1.5
  circle A22 centre (381, -156.5) radius 1.5
  circle A23 centre (381, -212.5) radius 1.5
  line L42 (372.5, -103) -> (322.5, -103) projected
  line L43 (394.5, -250) -> (394.5, -150) projected
  line L44 (204.5, -222.5) -> (204.5, -252.5) construction
  line L45 (184.5, -222.5) -> (184.5, -252.5)
  line L46 (224.5, -252.5) -> (224.5, -222.5)
  arc A24 (224.5, -222.5) -> (184.5, -222.5) centre (204.5, -222.5) ccw
  arc A25 (184.5, -252.5) -> (224.5, -252.5) centre (204.5, -252.5) ccw
  line L47 (254.5, -287.5) -> (254.5, -187.5) projected
  line L48 (38.825, -187.5) -> (138.825, -187.5)
  line L49 (138.825, -187.5) -> (138.825, -287.5)
  line L50 (138.825, -287.5) -> (38.825, -287.5)
  line L51 (38.825, -287.5) -> (38.825, -187.5)
  circle A26 centre (43.075, -192.5) radius 1.5
  circle A27 centre (134.575, -192.5) radius 1.5
  circle A28 centre (43.075, -282.5) radius 1.5
  circle A29 centre (134.575, -282.5) radius 1.5
  point P0 (0, 0)
  point P1 (-371.5, -243)
  point P2 (-280.4, -243)
  point P3 (-149.5, -205.5)
  point P4 (-250.4, -243)
  point P5 (-159.3, -243)
  point P6 (347.5, -247)
  point P7 (347.5, -297)
  point P8 (-104.675, -254.5)
  point P9 (-24.675, -243.9689)
  point P10 (346, -140.2703)
  point P11 (204.5, -237.5)
  point P12 (254.5, -237.5)
  point P13 (138.825, -237.5)
  point P14 (254.5, -237.5)
  dimension "d334" = 4
  dimension "d335" = 5.5
  dimension "d336" = 4
  dimension "d337" = 2.25
  dimension "d338" = 87.1
  dimension "d340" = 300
  dimension "d341" = 15
  dimension "d342" = 20
  dimension "d343" = 100
  dimension "d344" = 30
  dimension "d345" = 30
  dimension "d346" = 4
  dimension "d347" = 2.25
  dimension "d348" = 4
  dimension "d349" = 2.25
  dimension "d350" = 87.1
  dimension "d351" = 30
  dimension "d352" = 30
  dimension "d353" = 30
  dimension "d354" = 50
  dimension "d355" = 30
  dimension "d356" = 43
  dimension "d357" = 43
  dimension "d358" = 3.3
  dimension "d359" = 3.3
  dimension "d360" = 37
  dimension "d361" = 30
  dimension "d362" = 20
  dimension "d363" = 37
  dimension "d364" = 77
  dimension "d365" = 63
  dimension "d366" = 10
  dimension "d367" = 20
  dimension "d368" = 3
  dimension "d369" = 56
  dimension "d371" = 70
  dimension "d372" = 77
  dimension "d373" = 63
  dimension "d374" = 3
  dimension "d375" = 56
  dimension "d376" = 70
  dimension "d377" = 50
  dimension "d378" = 10
  dimension "d379" = 50
  dimension "d380" = 30
  dimension "d381" = 20
  dimension "d382" = 100
  dimension "d383" = 100
  dimension "d384" = 25
  dimension "d385" = 3
  dimension "d386" = 3
  dimension "d387" = 3
  dimension "d388" = 3
  dimension "d389" = 90
  dimension "d390" = 91.5
  dimension "d391" = 4.25
  dimension "d392" = 5
  constraints: 104 end point, 30 centre point, 28 point on circle, 28 tangent, 24 midpoint, 16 parallel, 9 point on line, 8 symmetric about line, 7 horizontal, 5 horizontal alignment, 4 perpendicular, 3 vertical alignment, 1 vertical, 8 other
  measures "d334" distance of L0.start L0.end
  measures "d335" diameter of A1
  measures "d336" distance of L3.start L3.end
  measures "d337" diameter of A3
  measures "d338" distance of L0.end L3.start
  measures "d340" distance of L7.start L7.end
  measures "d341" diameter of A5
  measures "d342" distance between parallel lines of L10 L9
  measures "d343" distance from line of L11 L7.start
  measures "d344" distance from line of L8 L3.start
  measures "d345" distance from line of L11 L0.end
  measures "d346" distance of L12.start L12.end
  measures "d347" diameter of A7
  measures "d348" distance of L15.start L15.end
  measures "d349" diameter of A9
  measures "d350" distance of L12.end L15.start
  measures "d351" distance of point (-280.4, -243) point (-250.4, -243)
  measures "d352" distance from line of L8 L12.end
  measures "d353" diameter of A11
  measures "d354" distance between parallel lines of L21 L18
  measures "d355" distance of L18.start L18.end
  measures "d356" distance of L23.end L24.end
  measures "d357" distance of L22.end L23.end
  measures "d358" diameter of A12
  measures "d359" diameter of A13
  measures "d360" distance of A13.centre A12.centre
  measures "d361" distance edge to line of A9 L25
  measures "d362" distance between parallel lines of L8 L24
  measures "d363" distance of A12.centre A14.centre
  measures "d364" distance of L30.start L30.end
  measures "d365" distance of L30.end L31.end
  measures "d366" distance between parallel lines of L8 L32
  measures "d367" distance between parallel lines of L23 L33
  measures "d368" diameter of A16
  measures "d369" distance of A17.centre A16.centre
  measures "d371" distance of A18.centre A16.centre
  measures "d372" distance of L39.end L36.end
  measures "d373" distance of L36.end L38.start
  measures "d374" diameter of A20
  measures "d375" distance of A21.centre A20.centre
  measures "d376" distance of A22.centre A20.centre
  measures "d377" distance between parallel lines of L42 L38
  measures "d378" distance between parallel lines of L43 L37
  measures "d379" distance between parallel lines of L47 L44
  measures "d380" distance of L44.start L44.end
  measures "d381" radius of A24
  measures "d382" distance of L48.end L49.end
  measures "d383" distance of L49.end L50.end
  measures "d384" distance between parallel lines of L31 L51
  measures "d385" diameter of A26
  measures "d386" diameter of A29
  measures "d387" diameter of A27
  measures "d388" diameter of A28
  measures "d389" distance between centres of A28 A26
  measures "d390" distance of A27.centre A26.centre
  measures "d391" distance from line of L49 A27.centre
  measures "d392" distance from line of L48 A27.centre
extrude "Extrusion9" cut sketch "Sketch13" against normal through all contours A0 L2 A1 L1 | A2 L5 A3 L4 | A4 L9 A5 L8 | A6 L14 A7 L13 | A8 L17 A9 L16 | A10 L20 A11 L19 | A12 | A13 | A14 | A15 | A16 | A17 | A18 | A19 | A20 | A21 | A22 | A23 | A24 L46 A25 L45 | A26 | A27 | A28 | A29
hole "Hole3" at (224, 7, -32) at (239, 7, -32) at (245, 7, -165) at (265, 7, -165) direction (0, -1, 0) diameter 3.6 end through all clearance for "Hex Head Cap Screw ISO 24017" size "M3" standard "ISO"
sketch "Sketch14" plane through (0, 7, 0) normal (0, 1, 0) x (1, 0, 0)
  line L0 (92, 53.5) -> (95, 53.5)
  line L1 (95, 53.5) -> (95, 47.5)
  line L2 (95, 47.5) -> (92, 47.5)
  line L3 (92, 47.5) -> (92, 53.5)
  line L4 (92, 122.5) -> (95, 122.5)
  line L5 (95, 122.5) -> (95, 116.5)
  line L6 (95, 116.5) -> (92, 116.5)
  line L7 (92, 116.5) -> (92, 122.5)
  line L8 (100, 121) -> (100, 124)
  line L9 (100, 124) -> (107.5, 124)
  line L10 (107.5, 124) -> (107.5, 121)
  line L11 (107.5, 121) -> (100, 121)
  line L12 (155, 124) -> (155, 121)
  line L13 (155, 121) -> (147.5, 121)
  line L14 (147.5, 121) -> (147.5, 124)
  line L15 (147.5, 124) -> (155, 124)
  line L16 (156.2155, 46) -> (146.2845, 46)
  line L17 (146.2845, 46) -> (146.2845, 49)
  line L18 (146.2845, 49) -> (156.2155, 49)
  line L19 (156.2155, 49) -> (156.2155, 46)
  line L20 (108.7155, 46) -> (98.7845, 46)
  line L21 (98.7845, 46) -> (98.7845, 49)
  line L22 (98.7845, 49) -> (108.7155, 49)
  line L23 (108.7155, 49) -> (108.7155, 46)
  point P0 (0, 0)
  constraints: 48 end point, 12 horizontal, 12 vertical, 24 other
extrude "Extrusion10" cut sketch "Sketch14" against normal through all